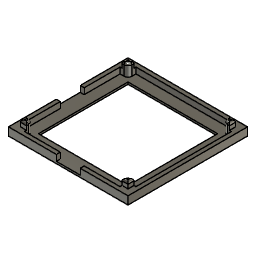
Light_Tile (Autodesk Fusion 360 design; units mm, degrees)
Autodesk Fusion 360 part; units mm, degrees
sketch "Sketch1" plane through (0, 0, 0) normal (0, 0, 1) x (1, 0, 0)
  line L0 (0, 0) -> (60, 0)
  line L1 (60, 0) -> (60, 60)
  line L2 (60, 60) -> (0, 60)
  line L3 (0, 60) -> (0, 0)
  line L4 (2, 2) -> (58, 2)
  line L5 (58, 2) -> (58, 58)
  line L6 (58, 58) -> (2, 58)
  line L7 (2, 58) -> (2, 2)
  line L8 (7.5, 7.5) -> (52.5, 7.5)
  line L9 (52.5, 7.5) -> (52.5, 52.5)
  line L10 (52.5, 52.5) -> (7.5, 52.5)
  line L11 (7.5, 52.5) -> (7.5, 7.5)
  dimension "d1" = 60
  dimension "d2" = 60
  dimension "d3" = 56
  dimension "d4" = 56
  dimension "d5" = 2
  dimension "d6" = 2
  dimension "d7" = 45
  dimension "d8" = 45
  dimension "d9" = 7.5
  dimension "d10" = 7.5
  constraint horizontal L0
  constraint vertical L1
  constraint horizontal L2
  constraint vertical L3
  constraint coincident L0.start L3.end
  constraint horizontal L4
  constraint vertical L5
  constraint horizontal L6
  constraint vertical L7
  constraint horizontal L8
  constraint vertical L9
  constraint horizontal L10
  constraint vertical L11
  measures "d1" distance of L0.start L0.end
  measures "d2" distance of L0.start L2.end
  measures "d3" distance of L4.start L4.end
  measures "d4" distance of L4.start L6.end
  measures "d5" distance of L3 L7
  measures "d6" distance of L0 L4
  measures "d7" distance of L8.start L8.end
  measures "d8" distance of L8.start L10.end
  measures "d9" distance of L2 L10
  measures "d10" distance of L1 L9
extrude "Extrude1" add sketch "Sketch1" along normal blind 1 contours L4 L5 L6 L7 makes body 1
extrude "Extrude2" add sketch "Sketch1" along normal blind 4 contours L0 L1 L2 L3 bodies 1
extrude "Extrude3" add 1 faces at (39.3333, 0.6667, 4) along direction (0, 0, 1) blind 7 separate body on bodies 1 makes body 2
sketch "Sketch2" plane through (0, 0, 11) normal (0, 0, 1) x (-1, 0, 0)
  line L0 (-2, -2) -> (-2, -58)
  line L1 (-2, -58) -> (-58, -58)
  line L2 (-58, -58) -> (-58, -2)
  line L3 (-58, -2) -> (-2, -2)
  line L4 (0, -60) -> (0, 0)
  line L5 (0, 0) -> (-60, 0)
  line L6 (-60, 0) -> (-60, -60)
  line L7 (-60, -60) -> (0, -60)
  line L8 (0, -60) -> (-60, -60)
  line L9 (-60, -60) -> (-60, 0)
  line L10 (-60, 0) -> (0, 0)
  line L11 (0, 0) -> (0, -60)
  constraint horizontal L8
  constraint vertical L9
  constraint horizontal L10
  constraint vertical L11
  constraint coincident L5.end L6.start
  constraint coincident L4.start L7.end
extrude "Extrude4" add sketch "Sketch2" along normal blind 0.12 separate body contours L0 L1 L2 L3 | L4 L5 L6 L7 L8 L9 L10 L11 makes body 3
sketch "Sketch3" plane through (0, 0, 11) normal (0, 0, -1) x (1, 0, 0)
  line L0 (60, 0) -> (0, 0)
  line L1 (0, 0) -> (0, -60)
  line L2 (0, -60) -> (60, -60)
  line L3 (60, -60) -> (60, 0)
  line L4 (2, -2) -> (58, -2)
  line L5 (58, -2) -> (58, -58)
  line L6 (58, -58) -> (2, -58)
  line L7 (2, -58) -> (2, -2)
  line L8 (2, -2) -> (7, -2)
  line L9 (7, -2) -> (7, -7)
  line L10 (7, -7) -> (2, -7)
  line L11 (2, -7) -> (2, -2)
  line L12 (58, -2) -> (53, -2)
  line L13 (53, -2) -> (53, -7)
  line L14 (53, -7) -> (58, -7)
  line L15 (58, -7) -> (58, -2)
  line L16 (2, -58) -> (7, -58)
  line L17 (7, -58) -> (7, -53)
  line L18 (7, -53) -> (2, -53)
  line L19 (2, -53) -> (2, -58)
  line L20 (58, -58) -> (53, -58)
  line L21 (53, -58) -> (53, -53)
  line L22 (53, -53) -> (58, -53)
  line L23 (58, -53) -> (58, -58)
  dimension "d19" = 56
  dimension "d20" = 56
  dimension "d21" = 5
  dimension "d22" = 5
  dimension "d23" = 5
  dimension "d24" = 5
  dimension "d25" = 5
  dimension "d26" = 5
  dimension "d27" = 5
  dimension "d28" = 5
  constraint horizontal L4
  constraint vertical L5
  constraint horizontal L6
  constraint vertical L7
  constraint horizontal L8
  constraint vertical L9
  constraint horizontal L10
  constraint vertical L11
  constraint horizontal L12
  constraint vertical L13
  constraint horizontal L14
  constraint vertical L15
  constraint horizontal L16
  constraint vertical L17
  constraint horizontal L18
  constraint vertical L19
  constraint horizontal L20
  constraint vertical L21
  constraint horizontal L22
  constraint vertical L23
  measures "d19" distance of L4.start L4.end
  measures "d20" distance of L4.start L6.end
  measures "d21" distance of L4.start L8.end
  measures "d22" distance of L4.start L10.end
  measures "d23" distance of L4.end L12.end
  measures "d24" distance of L4.end L14.end
  measures "d25" distance of L6.end L16.end
  measures "d26" distance of L6.end L18.end
  measures "d27" distance of L5.end L20.end
  measures "d28" distance of L5.end L22.end
extrude "Extrude5" add sketch "Sketch3" along normal blind 2 contours L4 L7 L8 L9 L10 L11 | L4 L5 L12 L13 L14 L15 | L6 L7 L16 L17 L18 L19 | L5 L6 L20 L21 L22 L23 bodies 3
extrude "Extrude6" cut 2 faces at (5.3333, 58, 10.3333) (56.3333, 58, 10.3333) along direction (0, -1, 0) blind 0.5 on bodies 3 bodies 3
extrude "Extrude7" cut 2 faces at (58, 54.5, 10.3333) (58, 3.6667, 10.3333) along direction (-1, 0, 0) blind 0.5 on bodies 3 bodies 3
extrude "Extrude8" cut 2 faces at (2, 5.3333, 10.3333) (2, 56, 10.3333) along direction (1, 0, 0) blind 0.5 on bodies 3 bodies 3
extrude "Extrude9" cut 2 faces at (4, 2, 10.3333) (54.5, 2, 10.3333) along direction (0, 1, 0) blind 0.5 on bodies 3 bodies 3
extrude "Extrude10" add 1 faces at (20, 40, 11.12) along direction (0, 0, 1) blind 0.12 on bodies 3 bodies 3
extrude "Extrude11" cut 4 faces at (54.5, 54.5, 9) (5.5, 56, 9) (4, 4, 9) (54.5, 4, 9) along direction (0, 0, 1) blind 0.5 on bodies 3 bodies 3
fillet "Fillet1" radius 3 4 edges at (53, 53, 10) (7, 53, 10) (7, 7, 10) (53, 7, 10) on bodies 3
fillet "Fillet3" radius 0.75 20 edges at (2.5, 55.25, 9.5) (4.75, 57.5, 9.5) (3.25, 53, 9.5) (6.1213, 53.8787, 9.5) (7, 56.75, 9.5) (2.5, 4.75, 9.5) (4.75, 2.5, 9.5) (7, 3.25, 9.5) (6.1213, 6.1213, 9.5) (3.25, 7, 9.5) (53, 56.75, 9.5) (53.8787, 53.8787, 9.5) (56.75, 53, 9.5) (55.25, 57.5, 9.5) (57.5, 55.25, 9.5) (55.25, 2.5, 9.5) (56.75, 7, 9.5) (53.8787, 6.1213, 9.5) (53, 3.25, 9.5) (57.5, 4.75, 9.5) on bodies 3
sketch "Sketch4" plane through (0, 0, 1) normal (0, 0, 1) x (-1, 0, 0)
  line L0 (-7.5, -7.5) -> (-7.5, -52.5)
  line L1 (-7.5, -52.5) -> (-52.5, -52.5)
  line L2 (-52.5, -52.5) -> (-52.5, -7.5)
  line L3 (-52.5, -7.5) -> (-7.5, -7.5)
  line L4 (-2, -58) -> (-2, -2)
  line L5 (-2, -2) -> (-58, -2)
  line L6 (-58, -2) -> (-58, -58)
  line L7 (-58, -58) -> (-2, -58)
  line L8 (-2, -58) -> (-58, -58)
  line L9 (-58, -58) -> (-58, -2)
  line L10 (-58, -2) -> (-2, -2)
  line L11 (-2, -2) -> (-2, -58)
  line L12 (-2, -58) -> (-6, -58)
  line L13 (-6, -58) -> (-6, -54)
  line L14 (-6, -54) -> (-2, -54)
  line L15 (-2, -54) -> (-2, -58)
  line L16 (-2, -2) -> (-6, -2)
  line L17 (-6, -2) -> (-6, -6)
  line L18 (-6, -6) -> (-2, -6)
  line L19 (-2, -6) -> (-2, -2)
  line L20 (-58, -2) -> (-54, -2)
  line L21 (-54, -2) -> (-54, -6)
  line L22 (-54, -6) -> (-58, -6)
  line L23 (-58, -6) -> (-58, -2)
  line L24 (-58, -58) -> (-54, -58)
  line L25 (-54, -58) -> (-54, -54)
  line L26 (-54, -54) -> (-58, -54)
  line L27 (-58, -54) -> (-58, -58)
  line L28 (-54, -54) -> (-57, -54)
  line L29 (-57, -54) -> (-57, -57)
  line L30 (-57, -57) -> (-54, -57)
  line L31 (-54, -57) -> (-54, -54)
  line L32 (-6, -54) -> (-3, -54)
  line L33 (-3, -54) -> (-3, -57)
  line L34 (-3, -57) -> (-6, -57)
  line L35 (-6, -57) -> (-6, -54)
  line L36 (-6, -6) -> (-3, -6)
  line L37 (-3, -6) -> (-3, -3)
  line L38 (-3, -3) -> (-6, -3)
  line L39 (-6, -3) -> (-6, -6)
  line L40 (-54, -6) -> (-57, -6)
  line L41 (-57, -6) -> (-57, -3)
  line L42 (-57, -3) -> (-54, -3)
  line L43 (-54, -3) -> (-54, -6)
  dimension "d49" = 4
  dimension "d50" = 4
  dimension "d51" = 4
  dimension "d52" = 4
  dimension "d53" = 4
  dimension "d54" = 3
  dimension "d55" = 3
  dimension "d56" = 3
  dimension "d57" = 3
  dimension "d58" = 3
  dimension "d59" = 3
  dimension "d60" = 3
  dimension "d61" = 3
  constraint horizontal L8
  constraint vertical L9
  constraint horizontal L10
  constraint vertical L11
  constraint coincident L4.start L7.end
  constraint horizontal L12
  constraint vertical L13
  constraint horizontal L14
  constraint vertical L15
  constraint horizontal L16
  constraint vertical L17
  constraint horizontal L18
  constraint vertical L19
  constraint horizontal L20
  constraint vertical L21
  constraint horizontal L22
  constraint vertical L23
  constraint horizontal L24
  constraint vertical L25
  constraint horizontal L26
  constraint vertical L27
  constraint coincident L6.end L7.start
  constraint horizontal L28
  constraint vertical L29
  constraint horizontal L30
  constraint vertical L31
  constraint horizontal L32
  constraint vertical L33
  constraint horizontal L34
  constraint vertical L35
  constraint horizontal L36
  constraint vertical L37
  constraint horizontal L38
  constraint vertical L39
  constraint horizontal L40
  constraint vertical L41
  constraint horizontal L42
  constraint vertical L43
  measures "d49" distance of L4.end L18.end
  measures "d50" distance of L5.end L20.end
  measures "d51" distance of L5.end L22.end
  measures "d52" distance of L6.end L24.end
  measures "d53" distance of L6.end L26.end
  measures "d54" distance of L25.end L28.end
  measures "d55" distance of L25.end L30.end
  measures "d56" distance of L13.end L32.end
  measures "d57" distance of L13.end L34.end
  measures "d58" distance of L17.end L36.end
  measures "d59" distance of L17.end L38.end
  measures "d60" distance of L21.end L40.end
  measures "d61" distance of L21.end L42.end
extrude "Extrude12" add sketch "Sketch4" along normal blind 3 contours L4 L7 L8 L11 L12 L13 L14 L15 L33 L34 | L4 L5 L10 L11 L16 L17 L18 L19 L37 L38 | L6 L7 L8 L9 L24 L25 L26 L27 L29 L30 | L5 L6 L9 L10 L20 L21 L22 L23 L41 L42 bodies 1
extrude "Extrude13" add sketch "Sketch4" along normal blind 6 contours L13 L14 L32 L33 L34 L35 | L17 L18 L36 L37 L38 L39 | L25 L26 L28 L29 L30 L31 | L21 L22 L40 L41 L42 L43 bodies 1
fillet "Fillet4" radius 2 4 edges at (54, 54, 4) (6, 54, 4) (54, 6, 4) (6, 6, 4) on bodies 1
fillet "Fillet5" radius 1 20 edges at (55.5, 3, 7) (57, 4.5, 7) (54, 3.5, 7) (54.5858, 5.4142, 7) (56.5, 6, 7) (57, 55.5, 7) (55.5, 57, 7) (56.5, 54, 7) (54.5858, 54.5858, 7) (54, 56.5, 7) (3, 55.5, 7) (4.5, 57, 7) (6, 56.5, 7) (5.4142, 54.5858, 7) (3.5, 54, 7) (3.5, 6, 7) (5.4142, 5.4142, 7) (6, 3.5, 7) (4.5, 3, 7) (3, 4.5, 7) on bodies 1
sketch "holes" plane through (0, 0, 4) normal (0, 0, 1) x (-1, 0, 0)
  line L0 (-2, -6) -> (-2, -54)
  line L1 (-2, -54) -> (-3, -54)
  line L2 (-3, -54) -> (-3, -57)
  line L3 (-3, -57) -> (-6, -57)
  line L4 (-6, -57) -> (-6, -58)
  line L5 (-6, -58) -> (-54, -58)
  line L6 (-54, -58) -> (-54, -57)
  line L7 (-54, -57) -> (-57, -57)
  line L8 (-57, -57) -> (-57, -54)
  line L9 (-57, -54) -> (-58, -54)
  line L10 (-58, -54) -> (-58, -6)
  line L11 (-58, -6) -> (-57, -6)
  line L12 (-57, -6) -> (-57, -3)
  line L13 (-57, -3) -> (-54, -3)
  line L14 (-54, -3) -> (-54, -2)
  line L15 (-54, -2) -> (-6, -2)
  line L16 (-6, -2) -> (-6, -3)
  line L17 (-6, -3) -> (-3, -3)
  line L18 (-3, -3) -> (-3, -6)
  line L19 (-3, -6) -> (-2, -6)
  line L20 (0, -60) -> (0, 0)
  line L21 (0, 0) -> (-60, 0)
  line L22 (-60, 0) -> (-60, -60)
  line L23 (-60, -60) -> (0, -60)
  line L24 (0, -30) -> (-60, -30)
  line L25 (-30, -30) -> (-30, 0)
  line L26 (0, -36) -> (-2, -36)
  line L27 (-2, -36) -> (-2, -24)
  line L28 (-2, -24) -> (0, -24)
  line L29 (0, -24) -> (0, -36)
  line L30 (-60, -36) -> (-58, -36)
  line L31 (-58, -36) -> (-58, -24)
  line L32 (-58, -24) -> (-60, -24)
  line L33 (-60, -24) -> (-60, -36)
  line L34 (-24, 0) -> (-36, 0)
  line L35 (-36, 0) -> (-36, -2)
  line L36 (-36, -2) -> (-24, -2)
  line L37 (-24, -2) -> (-24, 0)
  dimension "d70" = 12
  dimension "d71" = 6
  dimension "d72" = 12
  dimension "d73" = 6
  dimension "d74" = 12
  dimension "d75" = 6
  constraint midpoint L20 L24.start
  constraint midpoint L22 L24.end
  constraint midpoint L24 L25.start
  constraint midpoint L21 L25.end
  constraint horizontal L26
  constraint vertical L27
  constraint horizontal L28
  constraint vertical L29
  constraint coincident L20 L26.start
  constraint horizontal L30
  constraint vertical L31
  constraint horizontal L32
  constraint vertical L33
  constraint coincident L22 L30.start
  constraint horizontal L34
  constraint vertical L35
  constraint horizontal L36
  constraint vertical L37
  constraint coincident L21 L34.start
  measures "d70" distance of L26.start L28.end
  measures "d71" distance of L24 L26
  measures "d72" distance of L30.start L32.end
  measures "d73" distance of L24 L30
  measures "d74" distance of L34.start L34.end
  measures "d75" distance of L25 L37
extrude "Extrude14" cut sketch "holes" against normal blind 3 contours L0 L20 L24 L27 L28 L29 | L0 L20 L24 L26 L27 L29 | L10 L22 L24 L31 L32 L33 | L10 L22 L24 L30 L31 L33 bodies 1
extrude "Extrude15" cut sketch "holes" against normal blind 3 contours L15 L21 L25 L34 L36 L37 | L15 L21 L25 L34 L35 L36 bodies 1
extrude "Extrude16" add 1 faces at (59.3333, 36, 3) along direction (0, -1, 0) blind 12 on bodies 1 bodies 1
hidden bodies 2 3
named bodies: "bot", "mid", "dif"
